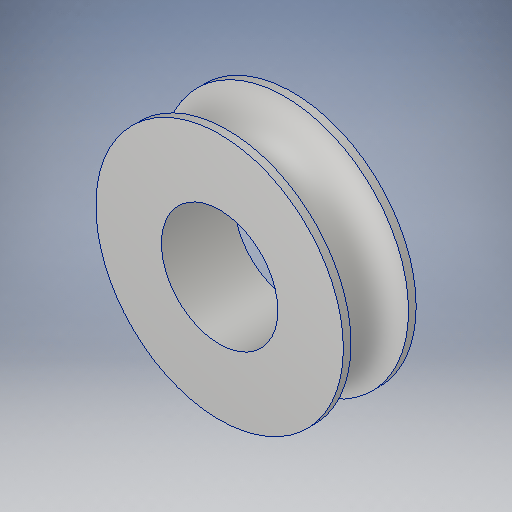
# Autodesk Inventor part: BT011_thutrn22_26
Saved by Autodesk Inventor 2025.3 (Build 293356000, 356)
## iProperties
Company: HTBLA Kaindorf
RuleStatus: InUse
Created: 2026-08-11
Part Number: BT011_thutrn22_26
Project: Biegeroboter
Material: Aluminium 6061
Description: Nadellager
Document SubType Name: Modeling
Designer: thutrn22
Density: 2.7 g/cm^3
Appearance: Aluminium - flach
Mass: 101.712 g
Surface Area: 130.804 cm^2
Volume: 37.6712 cm^3
AfterDocNew0: iProperties-Editor_aufrufen
Author: trist
Keywords: 2026
Autodesk Inventor part; units mm, degrees
ref_plane "YZ Plane" through (0, 0, 0) normal (1, 0, 0) x (0, 1, 0)
ref_plane "XZ Plane" through (0, 0, 0) normal (0, 1, 0) x (-1, 0, 0)
ref_plane "XY Plane" through (0, 0, 0) normal (0, 0, 1) x (1, 0, 0)
sketch "Skizze3" plane through (0, 0, 0) normal (0, 0, 1) x (1, 0, 0)
  line L0 (-25.1043, 0) -> (15.8507, 0) projected
  line L1 (0, -61.3404) -> (0, 10.2234) projected
  line L2 (-19.2536, -51.117) -> (0.7464, -51.117)
  line L3 (-10, -40.2505) -> (-10, -51.117)
  line L4 (-10, -51.117) -> (10, -51.117)
  line L5 (10, -51.117) -> (10, -17.117)
  line L6 (10, -17.117) -> (-10, -17.117)
  line L7 (-10, -17.117) -> (-10, -51.117)
  line L8 (-10, -51.117) -> (10, -51.117)
  line L9 (10, -51.117) -> (10, -35.117)
  line L10 (10, -35.117) -> (-10, -35.117)
  line L11 (-10, -35.117) -> (-10, -51.117)
  line L12 (-7, -17.117) -> (-7, -26.3642)
  line L13 (-7, -26.3642) -> (-10, -26.3642)
  line L14 (7, -17.117) -> (7, -27.3388)
  line L15 (7, -27.3388) -> (10, -27.3388)
  circle A0 centre (0, -17.117) radius 7.9
  point P0 (0, 0)
  point P1 (-5.2536, -23.017)
  point P2 (7.9, -17.117)
  point P3 (-7.9, -17.117)
  dimension "d11" = 15.8
  dimension "d4" = 20
  dimension "d5" = 34
  dimension "d6" = 20
  dimension "d7" = 16
  dimension "d8" = 3
  dimension "d9" = 3
  dimension "d12" = 28.1
  dimension "d15" = 34
  constraints: 28 end point, 5 parallel, 4 point on line, 3 perpendicular, 2 horizontal, 2 vertical, 1 collinear, 1 midpoint, 4 other
  measures "d4" distance of L6.end L6.start
  measures "d5" distance of L6.start L5.start
  measures "d6" distance of L10.end L10.start
  measures "d7" distance of L10.start L9.start
  measures "d8" distance between parallel lines of L7 L12
  measures "d9" distance between parallel lines of L5 L14
  measures "d12" distance from line of point (-5.254, -23.017) L8
  measures "d15" distance from line of L2 point (0, -17.117)
revolve "Umdrehung2" add sketch "Skizze3" angle 360 about axis through (-10, -51.117, 0) along (1, 0, 0) contours L10 L7 L13 L12 A0 L1 | L1 A0 L14 L15 L5 L10 | L12 L13 L7 L6 A0 | A0 L6 L5 L15 L14
